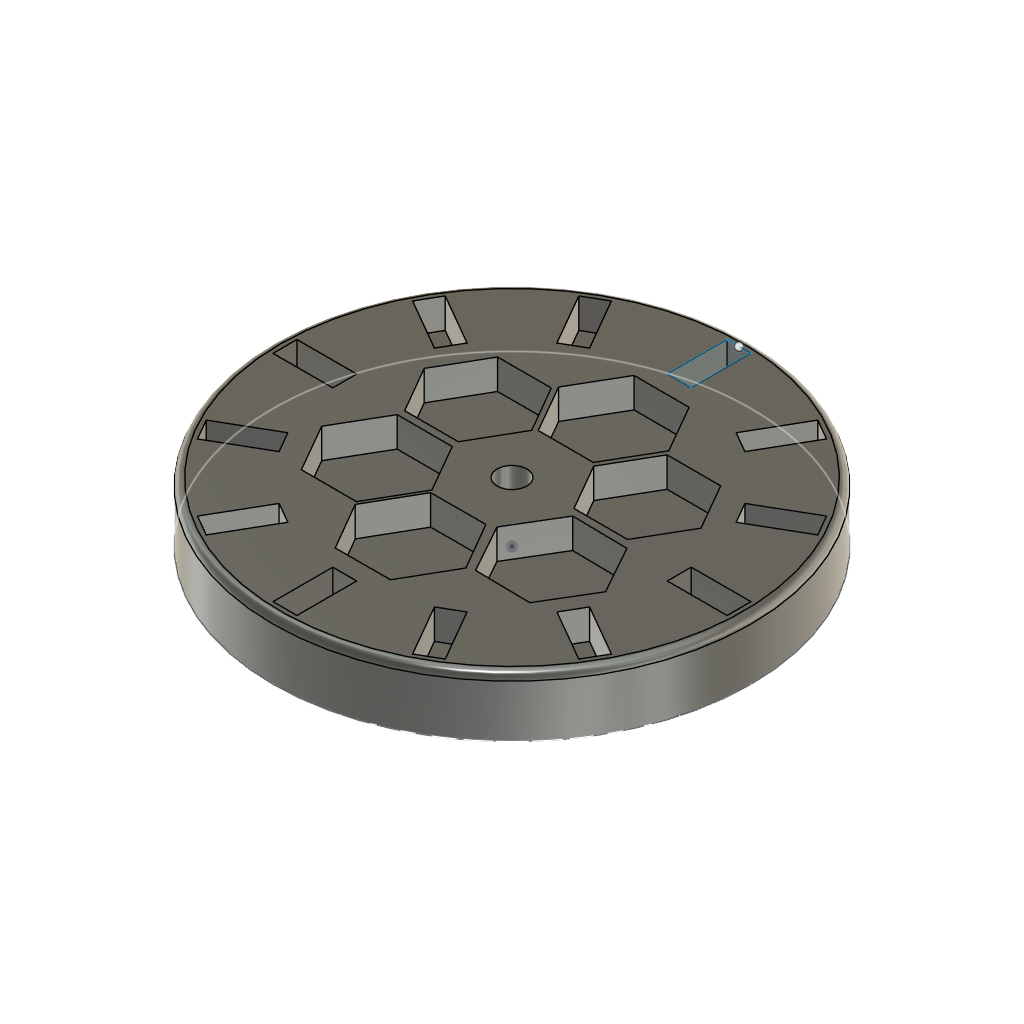
Bee Clock (Autodesk Fusion 360 design; units mm, degrees)
part number: 2026-11-12-09-29-17-187
Autodesk Fusion 360 part; units mm, degrees
sketch "Sketch1" plane through (0, 0, 0) normal (0, 0, 1) x (1, 0, 0)
  circle A0 centre (0, 0) radius 101.6
  dimension "d1" = 203.2
  constraint coincident A0.centre origin
  measures "d1" diameter of A0
extrude "Extrude1" add sketch "Sketch1" along normal blind 25.4
sketch "Sketch3" plane through (0, 0, 25.4) normal (0, 0, 1) x (-1, 0, 0)
  line L0 (-11.7318, 20.32) -> (-23.4635, 0)
  line L1 (-23.4635, 0) -> (-11.7318, -20.32)
  line L2 (-11.7318, -20.32) -> (11.7318, -20.32)
  line L3 (11.7318, -20.32) -> (23.4635, 0)
  line L4 (23.4635, 0) -> (11.7318, 20.32)
  line L5 (11.7318, 20.32) -> (-11.7318, 20.32)
  line L6 (-11.826, 63.4712) -> (-23.5131, 43.1255)
  line L7 (-23.5131, 43.1255) -> (-11.7367, 22.8313)
  line L8 (-11.7367, 22.8313) -> (11.7267, 22.8828)
  line L9 (11.7267, 22.8828) -> (23.4138, 43.2285)
  line L10 (23.4138, 43.2285) -> (11.6375, 63.5227)
  line L11 (11.6375, 63.5227) -> (-11.826, 63.4712)
  line L12 (-11.7367, -22.8313) -> (11.7267, -22.8828)
  line L13 (11.7267, -22.8828) -> (23.4138, -43.2285)
  line L14 (23.4138, -43.2285) -> (11.6375, -63.5227)
  line L15 (11.6375, -63.5227) -> (-11.826, -63.4712)
  line L16 (-11.826, -63.4712) -> (-23.5131, -43.1255)
  line L17 (-23.5131, -43.1255) -> (-11.7367, -22.8313)
  line L18 (-13.1784, -21.5606) -> (-24.5653, -1.7771)
  line L19 (-24.5653, -1.7771) -> (-47.3917, -1.7466)
  line L20 (-47.3917, -1.7466) -> (-58.8313, -21.4997)
  line L21 (-58.8313, -21.4997) -> (-47.4444, -41.2831)
  line L22 (-47.4444, -41.2831) -> (-24.618, -41.3136)
  line L23 (-24.618, -41.3136) -> (-13.1784, -21.5606)
  line L24 (-61.9464, 22.1612) -> (-62.0958, 22.4518)
  line L25 (-61.9464, 22.1612) -> (-50.5336, 1.6603)
  line L26 (-49.8985, 42.2954) -> (-61.9464, 22.1612)
  line L27 (-15.0251, 21.4278) -> (-26.4378, 41.9287)
  line L28 (-26.4378, 41.9287) -> (-49.8985, 42.2954)
  line L29 (-27.073, 1.2937) -> (-15.0251, 21.4278)
  line L30 (-27.073, 1.2937) -> (-50.5336, 1.6603)
  line L31 (24.5653, -1.7771) -> (47.3917, -1.7466)
  line L32 (13.1784, -21.5606) -> (24.5653, -1.7771)
  line L33 (24.618, -41.3136) -> (13.1784, -21.5606)
  line L34 (47.4444, -41.2831) -> (24.618, -41.3136)
  line L35 (58.8313, -21.4997) -> (47.4444, -41.2831)
  line L36 (47.3917, -1.7466) -> (58.8313, -21.4997)
  line L37 (24.0974, 1.3096) -> (47.5609, 1.2581)
  line L38 (24.0974, 1.3096) -> (12.4103, 21.6553)
  line L39 (12.4103, 21.6553) -> (24.1866, 41.9495)
  line L40 (24.1866, 41.9495) -> (47.6501, 41.898)
  line L41 (47.6501, 41.898) -> (59.3372, 21.5523)
  line L42 (59.3372, 21.5523) -> (47.5609, 1.2581)
  circle A0 centre (0, 0) radius 101.6
  point P0 (-0.0496, 43.177)
  point P1 (-38.4857, 21.7945)
  dimension "d14" = 20.32
  dimension "d15" = 20.32
  dimension "d33" = 20.32
  constraint coincident A0.centre origin
  measures "d14" distance of A0.centre L5
  measures "d15" distance of P0 L11
  measures "d33" distance of P1 L28
extrude "Extrude3" cut sketch "Sketch3" against normal blind 12.7 contours L6 L7 L8 L9 L10 L11 | L12 L13 L14 L15 L16 L17 | L18 L19 L20 L21 L22 L23 | L25 L26 L27 L28 L29 L30 | L31 L32 L33 L34 L35 L36 | L37 L38 L39 L40 L41 L42
sketch "Sketch4" plane through (0, 0, 25.4) normal (0, 0, 1) x (-1, 0, 0)
  line L0 (-24.5653, -1.7771) -> (-13.1784, -21.5606)
  line L1 (-13.1784, -21.5606) -> (-24.618, -41.3136)
  line L2 (-24.618, -41.3136) -> (-47.4444, -41.2831)
  line L3 (-47.4444, -41.2831) -> (-58.8313, -21.4997)
  line L4 (-58.8313, -21.4997) -> (-47.3917, -1.7466)
  line L5 (-47.3917, -1.7466) -> (-24.5653, -1.7771)
  line L6 (13.1784, -21.5606) -> (24.5653, -1.7771)
  line L7 (24.5653, -1.7771) -> (47.3917, -1.7466)
  line L8 (47.3917, -1.7466) -> (58.8313, -21.4997)
  line L9 (58.8313, -21.4997) -> (47.4444, -41.2831)
  line L10 (47.4444, -41.2831) -> (24.618, -41.3136)
  line L11 (24.618, -41.3136) -> (13.1784, -21.5606)
  line L12 (59.3372, 21.5523) -> (47.5609, 1.2581)
  line L13 (47.5609, 1.2581) -> (24.0974, 1.3096)
  line L14 (24.0974, 1.3096) -> (12.4103, 21.6553)
  line L15 (12.4103, 21.6553) -> (24.1866, 41.9495)
  line L16 (24.1866, 41.9495) -> (47.6501, 41.898)
  line L17 (47.6501, 41.898) -> (59.3372, 21.5523)
  line L18 (-49.8985, 42.2954) -> (-26.4378, 41.9287)
  line L19 (-26.4378, 41.9287) -> (-15.0251, 21.4278)
  line L20 (-15.0251, 21.4278) -> (-27.073, 1.2937)
  line L21 (-27.073, 1.2937) -> (-50.5336, 1.6603)
  line L22 (-50.5336, 1.6603) -> (-61.9464, 22.1612)
  line L23 (-61.9464, 22.1612) -> (-49.8985, 42.2954)
  line L24 (11.6375, -63.5227) -> (-11.826, -63.4712)
  line L25 (-11.826, -63.4712) -> (-23.5131, -43.1255)
  line L26 (-23.5131, -43.1255) -> (-11.7367, -22.8313)
  line L27 (-11.7367, -22.8313) -> (11.7267, -22.8828)
  line L28 (11.7267, -22.8828) -> (23.4138, -43.2285)
  line L29 (23.4138, -43.2285) -> (11.6375, -63.5227)
  line L30 (-23.5131, 43.1255) -> (-11.826, 63.4712)
  line L31 (-11.826, 63.4712) -> (11.6375, 63.5227)
  line L32 (11.6375, 63.5227) -> (23.4138, 43.2285)
  line L33 (23.4138, 43.2285) -> (11.7267, 22.8828)
  line L34 (11.7267, 22.8828) -> (-11.7367, 22.8313)
  line L35 (-11.7367, 22.8313) -> (-23.5131, 43.1255)
  circle A0 centre (0, 0) radius 6.35
  circle A1 centre (0, 0) radius 101.6
  dimension "d36" = 12.7
  constraint concentric A0 A1
  measures "d36" diameter of A0
extrude "Extrude4" cut sketch "Sketch4" against normal blind 25.4 contours A0
sketch "Sketch2" plane through (0, 0, 25.4) normal (0, 0, 1) x (-1, 0, 0)
  line L0 (0, -96.52) -> (5.08, -96.52)
  line L1 (5.08, -96.52) -> (-5.08, -96.52)
  line L2 (-5.08, -96.52) -> (-5.08, -71.12)
  line L3 (-5.08, -71.12) -> (5.08, -71.12)
  line L4 (5.08, -71.12) -> (5.08, -96.52)
  dimension "d42" = 5.08
  dimension "d43" = 25.4
  constraint horizontal L1
  constraint vertical L2
  constraint horizontal L3
  constraint vertical L4
  measures "d42" distance of L0.start L0.end
  measures "d43" distance of L0.end L3.end
extrude "Extrude5" cut sketch "Sketch2" against normal blind 12.7
pattern_circular "C-Pattern2" count 12 over 360 about axis through (0, 0, 1.75) along (0, 0, 1) of "Extrude5"
fillet "Fillet2" radius 3.175 1 edges at (-94.7245, -36.7401, 25.4)
